shaft-attachment (Autodesk Fusion 360 design; units mm, degrees)
part number: 2026-11-15-20-09-18-791
Autodesk Fusion 360 part; units mm, degrees
sketch "Sketch1" plane through (0, 0, 0) normal (0, 0, 1) x (1, 0, 0)
  arc A0 (-6.1499, -12.8546) -> (-5.2317, -13.2502) centre (-5.6951, -13.0625) ccw
  arc A1 (14.2149, -0.9998) -> (14.1711, 1.4979) centre (0, 0) ccw
  arc A2 (-14.1098, 1.9942) -> (-14.1974, 0.9986) centre (-14.1711, 1.4979) ccw
  arc A3 (14.1098, -1.9942) -> (14.2149, -0.9998) centre (14.1711, -1.4979) ccw
  circle A4 centre (0, 0) radius 4
  circle A5 centre (0, 0) radius 16.75
  arc A6 (-4, -11.3137) -> (4, -11.3137) centre (0, 0) ccw
  arc A7 (-14.1974, -0.9986) -> (-14.1098, -1.9942) centre (-14.1711, -1.4979) ccw
  arc A8 (6.1499, -12.8546) -> (14.1098, -1.9942) centre (0, 0) ccw
  arc A9 (6.1499, 12.8546) -> (5.2334, 13.2542) centre (5.6951, 13.0625) ccw
  arc A10 (-5.2334, 13.2542) -> (-6.1499, 12.8546) centre (-5.6951, 13.0625) ccw
  arc A11 (-6.1499, 12.8546) -> (-14.1098, 1.9942) centre (0, 0) ccw
  arc A12 (-14.1098, -1.9942) -> (-6.1499, -12.8546) centre (0, 0) ccw
  arc A13 (5, -13.344) -> (5.2334, -13.2542) centre (0, 0) ccw
  arc A14 (-5.2334, -13.2542) -> (-5, -13.344) centre (0, 0) ccw
  arc A15 (5.2334, 13.2542) -> (-5.2334, 13.2542) centre (0, 0) ccw
  arc A16 (5.2317, -13.2502) -> (6.1499, -12.8546) centre (5.6951, -13.0625) ccw
  line L0 (-5, -13.344) -> (-4, -11.3137)
  arc A17 (14.0311, 2.4879) -> (6.1499, 12.8546) centre (0, 0) ccw
  arc A18 (-14.2149, 0.9998) -> (-14.2149, -0.9998) centre (0, 0) ccw
  arc A19 (14.1711, 1.4979) -> (14.0311, 2.4879) centre (14.1098, 1.9942) ccw
  line L1 (5, -13.344) -> (4, -11.3137)
  circle A20 centre (0, 0) radius 7.5001
  circle A21 centre (0, 0) radius 15.75
  line L2 (1.5, 0) -> (1.5, -9.8363)
  circle A22 centre (0, 0) radius 9.95
  line L3 (-1.5, 0) -> (-1.5, -9.8363)
  line L4 (1.5, 0) -> (1.5, 9.8363)
  line L5 (-1.5, 0) -> (-1.5, 9.8363)
  circle A23 centre (0, 0) radius 11.5
  point P0 (-23, 23)
  point P1 (3.6, -5.1)
  point P2 (-14.1711, 1.4979)
  point P3 (14.1711, -1.4979)
  point P4 (14.1098, 1.9942)
  point P5 (-20, -15)
  point P6 (-20, 15)
  point P7 (-20, -15)
  point P8 (-20, 15)
  point P9 (1.5, 0)
  point P10 (-1.5, 0)
  point P11 (5, 0)
  point P12 (-5, 0)
  dimension "d1" = 28.5
  dimension "d2" = 24
  dimension "d3" = 1
  dimension "d4" = 1
  dimension "d5" = 1
  dimension "d6" = 1
  dimension "d7" = 1
  dimension "d8" = 1
  dimension "d9" = 1
  dimension "d10" = 1
  dimension "d11" = 31.5
  dimension "d12" = 33.5
  dimension "d13" = 5
  dimension "d14" = 5
  dimension "d15" = 1.5
  dimension "d16" = 1.5
  dimension "d41" = 19.9
  dimension "d42" = 23
  constraint concentric A6 A13
  constraint coincident P2 A2.centre
  constraint coincident A18.start A2
  constraint concentric A11 A18
  constraint coincident A18.end A7
  constraint concentric A12 A18
  constraint concentric A11 A15
  constraint concentric A15 A17
  constraint concentric A12 A14
  constraint coincident A14.start A0
  constraint coincident A13.end A16
  constraint concentric A8 A13
  constraint coincident P3 A8
  constraint coincident P4 A1
  constraint coincident P3 A3.centre
  constraint coincident P4 A19.centre
  constraint concentric A1 A17
  constraint concentric A1 A8
  constraint concentric A1 A20
  constraint concentric A15 A21
  constraint concentric A5 A12
  constraint coincident P7 P5
  constraint coincident P8 P6
  constraint coincident P9 L2.start
  constraint coincident L2.end A22
  constraint vertical L2
  constraint coincident P10 L3.start
  constraint coincident L3.end A22
  constraint parallel L2 L3
  constraint coincident L5.end A22
  constraint parallel L3 L5
  constraint coincident L4.end A22
  constraint parallel L2 L4
  constraint concentric A18 A23
  measures "d1" diameter of A13
  measures "d2" diameter of A6
  measures "d3" diameter of A0
  measures "d4" diameter of A16
  measures "d5" diameter of A9
  measures "d6" diameter of A10
  measures "d7" diameter of A2
  measures "d8" diameter of A7
  measures "d9" diameter of A3
  measures "d10" diameter of A19
  measures "d11" diameter of A21
  measures "d12" diameter of A5
  measures "d13" distance of A1.centre P11
  measures "d14" distance of A1.centre P12
  measures "d15" distance of P9 A1.centre
  measures "d16" distance of P10 A1.centre
  measures "d41" diameter of A22
  measures "d42" diameter of A23
extrude "Extrude1" add sketch "Sketch1" against normal blind 35 contours A0 A1 A2 A3 A6 A7 A8 A9 A10 A11 A12 A13 A14 A15 A16 L0 A17 A18 A19 L1 | A4 L2 L4 | A4 A20 L2 L4 | A4 L2 L3 L4 L5 | A4 A20 L4 L5 | A4 A20 L2 L3 | A4 L3 L5 | A4 A20 L3 L5 | A20 L2 A22 L4 | A20 A22 L4 L5 | A20 L2 A22 L3 | A20 A22 L3 L5 | A23
extrude "Extrude2" cut sketch "Sketch1" against normal blind 3.1 contours A4 L2 L4 | A4 A20 L2 L4 | A4 L3 L5 | A4 A20 L3 L5 | A20 L2 A22 L4 | A20 A22 L3 L5
hole "Hole1" at (-5, 0, 0) at (5, 0, 0) direction (0, 0, -1) diameter 2.8 depth 35 tip angle 180
extrude "Extrude3" add sketch "Sketch1" against normal blind 1.6 contours A21
extrude "Extrude4" add sketch "Sketch1" along normal blind 0.5 contours A4 L2 L3 L4 L5 | A4 A20 L4 L5 | A4 A20 L2 L3 | A20 A22 L4 L5 | A20 L2 A22 L3
extrude "Extrude5" add 1 faces at (2.2013, -0.0349, -3.1) along direction (0, 0, 1) blind 0.5
extrude "Extrude6" add 1 faces at (-2.2013, 0.0349, -3.1) along direction (0, 0, 1) blind 0.5
extrude "Extrude7" add sketch "Sketch1" along normal blind 0.5 contours A23
extrude "Extrude8" cut sketch "Sketch1" against normal blind 0.5 contours A21
extrude "Extrude9" add 1 faces at (2.3705, -14.2708, -1.6) along direction (0, 0, -1) blind 0.5
extrude "Extrude10" cut 1 faces at (0, 5.5212, -35) along direction (0, 0, 1) blind 12.9
fillet "Fillet1" radius 0.75 1 edges at (-14.6842, 5.6954, -0.5)
extrude "Extrude11" cut 1 faces at (-6.5968, -11.56, 0) along direction (0, 0, -1) blind 0.5
